Autodesk Fusion 360 part; units mm, degrees
(part 2 of 2)
equation "d66 = ( ( ( layoutGap + keycapSize / 2 + 0 * keyPitch ) - switchOpening / 2 ) + ( switchOpening ) ) - ( ( layoutGap + keycapSize / 2 + 0 * keyPitch ) - switchOpening / 2 )"
equation "d67 = ( ( ( ( keyRowOne ) - switchOpening / 2 ) + faceOriginV ) + ( switchOpening ) ) - ( ( ( keyRowOne ) - switchOpening / 2 ) + faceOriginV )"
equation "d68 = -( carrierThickness + 1 mm )"
equation "d70 = ( layoutGap + keycapSize / 2 + 0 * keyPitch ) - upperSwitchOpening / 2"
equation "d71 = ( ( keyRowOne ) - upperSwitchOpening / 2 ) + faceOriginV"
equation "d72 = ( ( ( layoutGap + keycapSize / 2 + 0 * keyPitch ) - upperSwitchOpening / 2 ) + ( upperSwitchOpening ) ) - ( ( layoutGap + keycapSize / 2 + 0 * keyPitch ) - upperSwitchOpening / 2 )"
equation "d73 = ( ( ( ( keyRowOne ) - upperSwitchOpening / 2 ) + faceOriginV ) + ( upperSwitchOpening ) ) - ( ( ( keyRowOne ) - upperSwitchOpening / 2 ) + faceOriginV )"
equation "d74 = -( shellWall + 1 mm )"
equation "d76 = ( layoutGap + keycapSize / 2 + 1 * keyPitch ) - switchOpening / 2"
equation "d77 = ( ( keyRowOne ) - switchOpening / 2 ) + faceOriginV"
equation "d78 = ( ( ( layoutGap + keycapSize / 2 + 1 * keyPitch ) - switchOpening / 2 ) + ( switchOpening ) ) - ( ( layoutGap + keycapSize / 2 + 1 * keyPitch ) - switchOpening / 2 )"
equation "d79 = ( ( ( ( keyRowOne ) - switchOpening / 2 ) + faceOriginV ) + ( switchOpening ) ) - ( ( ( keyRowOne ) - switchOpening / 2 ) + faceOriginV )"
equation "d80 = -( carrierThickness + 1 mm )"
equation "d82 = ( layoutGap + keycapSize / 2 + 1 * keyPitch ) - upperSwitchOpening / 2"
equation "d83 = ( ( keyRowOne ) - upperSwitchOpening / 2 ) + faceOriginV"
equation "d84 = ( ( ( layoutGap + keycapSize / 2 + 1 * keyPitch ) - upperSwitchOpening / 2 ) + ( upperSwitchOpening ) ) - ( ( layoutGap + keycapSize / 2 + 1 * keyPitch ) - upperSwitchOpening / 2 )"
equation "d85 = ( ( ( ( keyRowOne ) - upperSwitchOpening / 2 ) + faceOriginV ) + ( upperSwitchOpening ) ) - ( ( ( keyRowOne ) - upperSwitchOpening / 2 ) + faceOriginV )"
equation "d86 = -( shellWall + 1 mm )"
equation "d88 = ( layoutGap + keycapSize / 2 + 2 * keyPitch ) - switchOpening / 2"
equation "d89 = ( ( keyRowOne ) - switchOpening / 2 ) + faceOriginV"
equation "d90 = ( ( ( layoutGap + keycapSize / 2 + 2 * keyPitch ) - switchOpening / 2 ) + ( switchOpening ) ) - ( ( layoutGap + keycapSize / 2 + 2 * keyPitch ) - switchOpening / 2 )"
equation "d91 = ( ( ( ( keyRowOne ) - switchOpening / 2 ) + faceOriginV ) + ( switchOpening ) ) - ( ( ( keyRowOne ) - switchOpening / 2 ) + faceOriginV )"
equation "d92 = -( carrierThickness + 1 mm )"
equation "d94 = ( layoutGap + keycapSize / 2 + 2 * keyPitch ) - upperSwitchOpening / 2"
equation "d95 = ( ( keyRowOne ) - upperSwitchOpening / 2 ) + faceOriginV"
equation "d96 = ( ( ( layoutGap + keycapSize / 2 + 2 * keyPitch ) - upperSwitchOpening / 2 ) + ( upperSwitchOpening ) ) - ( ( layoutGap + keycapSize / 2 + 2 * keyPitch ) - upperSwitchOpening / 2 )"
equation "d97 = ( ( ( ( keyRowOne ) - upperSwitchOpening / 2 ) + faceOriginV ) + ( upperSwitchOpening ) ) - ( ( ( keyRowOne ) - upperSwitchOpening / 2 ) + faceOriginV )"
equation "d98 = -( shellWall + 1 mm )"
equation "d100 = ( layoutGap + keycapSize / 2 + 0 * keyPitch ) - switchOpening / 2"
equation "d101 = ( ( keyRowTwo ) - switchOpening / 2 ) + faceOriginV"
equation "d102 = ( ( ( layoutGap + keycapSize / 2 + 0 * keyPitch ) - switchOpening / 2 ) + ( switchOpening ) ) - ( ( layoutGap + keycapSize / 2 + 0 * keyPitch ) - switchOpening / 2 )"
equation "d103 = ( ( ( ( keyRowTwo ) - switchOpening / 2 ) + faceOriginV ) + ( switchOpening ) ) - ( ( ( keyRowTwo ) - switchOpening / 2 ) + faceOriginV )"
equation "d104 = -( carrierThickness + 1 mm )"
equation "d106 = ( layoutGap + keycapSize / 2 + 0 * keyPitch ) - upperSwitchOpening / 2"
equation "d107 = ( ( keyRowTwo ) - upperSwitchOpening / 2 ) + faceOriginV"
equation "d108 = ( ( ( layoutGap + keycapSize / 2 + 0 * keyPitch ) - upperSwitchOpening / 2 ) + ( upperSwitchOpening ) ) - ( ( layoutGap + keycapSize / 2 + 0 * keyPitch ) - upperSwitchOpening / 2 )"
equation "d109 = ( ( ( ( keyRowTwo ) - upperSwitchOpening / 2 ) + faceOriginV ) + ( upperSwitchOpening ) ) - ( ( ( keyRowTwo ) - upperSwitchOpening / 2 ) + faceOriginV )"
equation "d110 = -( shellWall + 1 mm )"
equation "d112 = ( layoutGap + keycapSize / 2 + 1 * keyPitch ) - switchOpening / 2"
equation "d113 = ( ( keyRowTwo ) - switchOpening / 2 ) + faceOriginV"
equation "d114 = ( ( ( layoutGap + keycapSize / 2 + 1 * keyPitch ) - switchOpening / 2 ) + ( switchOpening ) ) - ( ( layoutGap + keycapSize / 2 + 1 * keyPitch ) - switchOpening / 2 )"
equation "d115 = ( ( ( ( keyRowTwo ) - switchOpening / 2 ) + faceOriginV ) + ( switchOpening ) ) - ( ( ( keyRowTwo ) - switchOpening / 2 ) + faceOriginV )"
equation "d116 = -( carrierThickness + 1 mm )"
equation "d118 = ( layoutGap + keycapSize / 2 + 1 * keyPitch ) - upperSwitchOpening / 2"
equation "d119 = ( ( keyRowTwo ) - upperSwitchOpening / 2 ) + faceOriginV"
equation "d120 = ( ( ( layoutGap + keycapSize / 2 + 1 * keyPitch ) - upperSwitchOpening / 2 ) + ( upperSwitchOpening ) ) - ( ( layoutGap + keycapSize / 2 + 1 * keyPitch ) - upperSwitchOpening / 2 )"
equation "d121 = ( ( ( ( keyRowTwo ) - upperSwitchOpening / 2 ) + faceOriginV ) + ( upperSwitchOpening ) ) - ( ( ( keyRowTwo ) - upperSwitchOpening / 2 ) + faceOriginV )"
equation "d122 = -( shellWall + 1 mm )"
equation "d124 = ( layoutGap + keycapSize / 2 + 2 * keyPitch ) - switchOpening / 2"
equation "d125 = ( ( keyRowTwo ) - switchOpening / 2 ) + faceOriginV"
equation "d126 = ( ( ( layoutGap + keycapSize / 2 + 2 * keyPitch ) - switchOpening / 2 ) + ( switchOpening ) ) - ( ( layoutGap + keycapSize / 2 + 2 * keyPitch ) - switchOpening / 2 )"
equation "d127 = ( ( ( ( keyRowTwo ) - switchOpening / 2 ) + faceOriginV ) + ( switchOpening ) ) - ( ( ( keyRowTwo ) - switchOpening / 2 ) + faceOriginV )"
equation "d128 = -( carrierThickness + 1 mm )"
equation "d130 = ( layoutGap + keycapSize / 2 + 2 * keyPitch ) - upperSwitchOpening / 2"
equation "d131 = ( ( keyRowTwo ) - upperSwitchOpening / 2 ) + faceOriginV"
equation "d132 = ( ( ( layoutGap + keycapSize / 2 + 2 * keyPitch ) - upperSwitchOpening / 2 ) + ( upperSwitchOpening ) ) - ( ( layoutGap + keycapSize / 2 + 2 * keyPitch ) - upperSwitchOpening / 2 )"
equation "d133 = ( ( ( ( keyRowTwo ) - upperSwitchOpening / 2 ) + faceOriginV ) + ( upperSwitchOpening ) ) - ( ( ( keyRowTwo ) - upperSwitchOpening / 2 ) + faceOriginV )"
equation "d134 = -( shellWall + 1 mm )"
equation "d136 = ( caseWidth - ledWidth ) / 2"
equation "d137 = ( ledCenter - ledHeight / 2 ) + faceOriginV"
equation "d138 = ( ( ( caseWidth - ledWidth ) / 2 ) + ( ledWidth ) ) - ( ( caseWidth - ledWidth ) / 2 )"
equation "d139 = ( ( ( ledCenter - ledHeight / 2 ) + faceOriginV ) + ( ledHeight ) ) - ( ( ledCenter - ledHeight / 2 ) + faceOriginV )"
equation "d140 = -( shellWall + 1 mm )"
equation "d142 = layoutGap"
equation "d143 = ( controlCenter - displayHeight / 2 ) + faceOriginV"
equation "d144 = ( ( layoutGap ) + ( displayWidth ) ) - ( layoutGap )"
equation "d145 = ( ( ( controlCenter - displayHeight / 2 ) + faceOriginV ) + ( displayHeight ) ) - ( ( controlCenter - displayHeight / 2 ) + faceOriginV )"
equation "d146 = -( shellWall + 1 mm )"
equation "d148 = encoderCenterX"
equation "d149 = controlCenter + faceOriginV"
equation "d150 = encoderHole"
equation "d151 = -( shellWall + 1 mm )"
equation "d153 = ( ( 0 mm ) + ( caseWidth ) ) - ( 0 mm )"
equation "d154 = ( ( 0 mm ) + ( caseLength ) ) - ( 0 mm )"
equation "d155 = bottomThickness"
equation "d157 = ( caseWidth - ledWidth ) / 2 + diffuserClearance"
equation "d158 = ( ledCenter - ledHeight / 2 + diffuserClearance ) + faceOriginV"
equation "d159 = ( ( ( caseWidth - ledWidth ) / 2 + diffuserClearance ) + ( ledWidth - 2 * diffuserClearance ) ) - ( ( caseWidth - ledWidth ) / 2 + diffuserClearance )"
equation "d160 = ( ( ( ledCenter - ledHeight / 2 + diffuserClearance ) + faceOriginV ) + ( ledHeight - 2 * diffuserClearance ) ) - ( ( ledCenter - ledHeight / 2 + diffuserClearance ) + faceOriginV )"
equation "d161 = -( shellWall )"
equation "d163 = -shellWall"
equation "d165 = ( caseWidth - ledWidth ) / 2 + diffuserClearance - diffuserFlange"
equation "d166 = ( ledCenter - ledHeight / 2 + diffuserClearance - diffuserFlange ) + faceOriginV"
equation "d167 = ( ( ( caseWidth - ledWidth ) / 2 + diffuserClearance - diffuserFlange ) + ( ledWidth - 2 * diffuserClearance + 2 * diffuserFlange ) ) - ( ( caseWidth - ledWidth ) / 2 + diffuserClearance - diffuserFlange )"
equation "d168 = ( ( ( ledCenter - ledHeight / 2 + diffuserClearance - diffuserFlange ) + faceOriginV ) + ( ledHeight - 2 * diffuserClearance + 2 * diffuserFlange ) ) - ( ( ledCenter - ledHeight / 2 + diffuserClearance - diffuserFlange ) + faceOriginV )"
equation "d169 = -( diffuserFlangeThickness )"
equation "carrierFaceLength = faceLength - 2 * ( shellWall + carrierClearance ) / cos(caseTilt) - carrierThickness * tan(caseTilt)" comment "Carrier rear clearance"
equation "d172 = layoutGap + 0 * keyPitch"
equation "d173 = ( keyRowOne - keycapSize / 2 ) + faceOriginV"
equation "d174 = ( ( layoutGap + 0 * keyPitch ) + ( keycapSize ) ) - ( layoutGap + 0 * keyPitch )"
equation "d175 = ( ( ( keyRowOne - keycapSize / 2 ) + faceOriginV ) + ( keycapSize ) ) - ( ( keyRowOne - keycapSize / 2 ) + faceOriginV )"
equation "d176 = layoutGap + 1 * keyPitch"
equation "d177 = ( keyRowOne - keycapSize / 2 ) + faceOriginV"
equation "d178 = ( ( layoutGap + 1 * keyPitch ) + ( keycapSize ) ) - ( layoutGap + 1 * keyPitch )"
equation "d179 = ( ( ( keyRowOne - keycapSize / 2 ) + faceOriginV ) + ( keycapSize ) ) - ( ( keyRowOne - keycapSize / 2 ) + faceOriginV )"
equation "d180 = layoutGap + 2 * keyPitch"
equation "d181 = ( keyRowOne - keycapSize / 2 ) + faceOriginV"
equation "d182 = ( ( layoutGap + 2 * keyPitch ) + ( keycapSize ) ) - ( layoutGap + 2 * keyPitch )"
equation "d183 = ( ( ( keyRowOne - keycapSize / 2 ) + faceOriginV ) + ( keycapSize ) ) - ( ( keyRowOne - keycapSize / 2 ) + faceOriginV )"
equation "d184 = layoutGap + 0 * keyPitch"
equation "d185 = ( keyRowTwo - keycapSize / 2 ) + faceOriginV"
equation "d186 = ( ( layoutGap + 0 * keyPitch ) + ( keycapSize ) ) - ( layoutGap + 0 * keyPitch )"
equation "d187 = ( ( ( keyRowTwo - keycapSize / 2 ) + faceOriginV ) + ( keycapSize ) ) - ( ( keyRowTwo - keycapSize / 2 ) + faceOriginV )"
equation "d188 = layoutGap + 1 * keyPitch"
equation "d189 = ( keyRowTwo - keycapSize / 2 ) + faceOriginV"
equation "d190 = ( ( layoutGap + 1 * keyPitch ) + ( keycapSize ) ) - ( layoutGap + 1 * keyPitch )"
equation "d191 = ( ( ( keyRowTwo - keycapSize / 2 ) + faceOriginV ) + ( keycapSize ) ) - ( ( keyRowTwo - keycapSize / 2 ) + faceOriginV )"
equation "d192 = layoutGap + 2 * keyPitch"
equation "d193 = ( keyRowTwo - keycapSize / 2 ) + faceOriginV"
equation "d194 = ( ( layoutGap + 2 * keyPitch ) + ( keycapSize ) ) - ( layoutGap + 2 * keyPitch )"
equation "d195 = ( ( ( keyRowTwo - keycapSize / 2 ) + faceOriginV ) + ( keycapSize ) ) - ( ( keyRowTwo - keycapSize / 2 ) + faceOriginV )"
equation "d196 = encoderCenterX"
equation "d197 = controlCenter + faceOriginV"
equation "d198 = encoderKnobDiameter"
equation "flangePocketClearance = 0.2 mm" comment "Carrier pocket clearance"
equation "d200 = ( caseWidth - ledWidth ) / 2 + diffuserClearance - diffuserFlange - flangePocketClearance"
equation "d201 = ( ledCenter - ledHeight / 2 + diffuserClearance - diffuserFlange - flangePocketClearance ) + faceOriginV"
equation "d202 = ( ( ( caseWidth - ledWidth ) / 2 + diffuserClearance - diffuserFlange - flangePocketClearance ) + ( ledWidth - 2 * diffuserClearance + 2 * diffuserFlange + 2 * flangePocketClearance ) ) - ( ( caseWidth - ledWidth ) / 2 + diffuserClearance - diffuserFlange - flangePocketClearance )"
equation "d203 = ( ( ( ledCenter - ledHeight / 2 + diffuserClearance - diffuserFlange - flangePocketClearance ) + faceOriginV ) + ( ledHeight - 2 * diffuserClearance + 2 * diffuserFlange + 2 * flangePocketClearance ) ) - ( ( ledCenter - ledHeight / 2 + diffuserClearance - diffuserFlange - flangePocketClearance ) + faceOriginV )"
equation "d204 = -( diffuserFlangeThickness - carrierClearance + flangePocketClearance )"
equation "carrierBayWidth = min(caseWidth - 2 * ( shellWall + carrierClearance + carrierRim ); ledWidth - 2 * diffuserClearance + 2 * diffuserFlange - 2 mm)" comment "Electronics opening preserving diffuser support rails"
equation "mountSideX = 4.8 mm" comment "Carrier fastener center from side"
equation "mountFrontV = 8 mm" comment "Front fastener center in face coordinates"
equation "mountRearV = faceLength - 8.4 mm" comment "Rear fastener center in face coordinates"
equation "mountBossDiameter = 7 mm" comment "Wall-connected M2 boss diameter"
equation "insertLength = 4 mm" comment "Confirmed M2 insert length"
equation "insertOuterDiameter = 3.5 mm" comment "Confirmed M2 insert outer diameter"
equation "insertPilotDiameter = 3.2 mm" comment "Provisional PLA pilot; test coupon required"
equation "insertPilotDepth = insertLength + 0.5 mm" comment "Blind insert pocket depth"
equation "carrierBossDepth = 7.4 mm" comment "Shell boss bottom below exterior face"
equation "carrierPadDepth = 10 mm" comment "Carrier pad bottom below exterior face"
equation "mountPocketClearance = 0.3 mm + ( carrierBossDepth - shellWall - carrierClearance ) * tan(caseTilt)" comment "Per-side carrier boss clearance"
equation "mountPadWidth = 7.8 mm" comment "Carrier mounting pad width"
equation "mountPadLength = 9.4 mm" comment "Carrier mounting pad length"
equation "m2Clearance = 2.3 mm" comment "Draft M2 screw clearance"
equation "bottomBossHeight = 6 mm" comment "Independent cover boss height above lid"
equation "carrierRibWidth = 2 mm" comment "Switch-field reinforcing rib width"
equation "carrierRibDepth = 3 mm" comment "Reinforcement below switch plate"
equation "d224 = -carrierBossDepth"
equation "d226 = -( carrierBossDepth + carrierClearance )"
equation "d228 = bottomThickness"
equation "d230 = mountSideX"
equation "d231 = ( mountFrontV ) + faceOriginV"
equation "d232 = mountBossDiameter"
equation "d233 = -( carrierBossDepth )"
equation "d235 = mountSideX"
equation "d236 = ( mountFrontV ) + faceOriginV"
equation "d237 = insertPilotDiameter"
equation "d238 = insertPilotDepth"
equation "d240 = shellWall + carrierClearance"
equation "d241 = ( ( mountFrontV ) - mountPadLength / 2 ) + faceOriginV"
equation "d242 = ( ( shellWall + carrierClearance ) + ( mountPadWidth ) ) - ( shellWall + carrierClearance )"
equation "d243 = ( ( ( ( mountFrontV ) - mountPadLength / 2 ) + faceOriginV ) + ( mountPadLength ) ) - ( ( ( mountFrontV ) - mountPadLength / 2 ) + faceOriginV )"
equation "d244 = -( carrierPadDepth - shellWall - carrierClearance )"
equation "d246 = mountSideX"
equation "d247 = ( mountFrontV ) + faceOriginV"
equation "d248 = mountBossDiameter + 2 * mountPocketClearance"
equation "d249 = carrierBossDepth + carrierClearance"
equation "d251 = mountSideX"
equation "d252 = ( mountFrontV ) + faceOriginV"
equation "d253 = m2Clearance"
equation "d254 = -( carrierPadDepth )"
equation "d258 = bottomBossDiameter"
equation "d259 = bottomBossHeight"
equation "d263 = insertPilotDiameter"
equation "d264 = insertPilotDepth"
equation "d268 = m2Clearance"
equation "d269 = -( bottomThickness + 0.5 mm )"
equation "d271 = caseWidth - mountSideX"
equation "d272 = ( mountFrontV ) + faceOriginV"
equation "d273 = mountBossDiameter"
equation "d274 = -( carrierBossDepth )"
equation "d276 = caseWidth - mountSideX"
equation "d277 = ( mountFrontV ) + faceOriginV"
equation "d278 = insertPilotDiameter"
equation "d279 = insertPilotDepth"
equation "d281 = caseWidth - shellWall - carrierClearance - mountPadWidth"
equation "d282 = ( ( mountFrontV ) - mountPadLength / 2 ) + faceOriginV"
equation "d283 = ( ( caseWidth - shellWall - carrierClearance - mountPadWidth ) + ( mountPadWidth ) ) - ( caseWidth - shellWall - carrierClearance - mountPadWidth )"
equation "d284 = ( ( ( ( mountFrontV ) - mountPadLength / 2 ) + faceOriginV ) + ( mountPadLength ) ) - ( ( ( mountFrontV ) - mountPadLength / 2 ) + faceOriginV )"
equation "d285 = -( carrierPadDepth - shellWall - carrierClearance )"
equation "d287 = caseWidth - mountSideX"
equation "d288 = ( mountFrontV ) + faceOriginV"
equation "d289 = mountBossDiameter + 2 * mountPocketClearance"
equation "d290 = carrierBossDepth + carrierClearance"
equation "d292 = caseWidth - mountSideX"
equation "d293 = ( mountFrontV ) + faceOriginV"
equation "d294 = m2Clearance"
equation "d295 = -( carrierPadDepth )"
equation "d297 = caseWidth - 20 mm"
equation "d299 = bottomBossDiameter"
equation "d300 = bottomBossHeight"
equation "d302 = caseWidth - 20 mm"
equation "d304 = insertPilotDiameter"
equation "d305 = insertPilotDepth"
equation "d307 = caseWidth - 20 mm"
equation "d309 = m2Clearance"
equation "d310 = -( bottomThickness + 0.5 mm )"
equation "d312 = mountSideX"
equation "d313 = ( mountRearV ) + faceOriginV"
equation "d314 = mountBossDiameter"
equation "d315 = -( carrierBossDepth )"
equation "d317 = mountSideX"
equation "d318 = ( mountRearV ) + faceOriginV"
equation "d319 = insertPilotDiameter"
equation "d320 = insertPilotDepth"
equation "d322 = shellWall + carrierClearance"
equation "d323 = ( ( mountRearV ) - mountPadLength / 2 ) + faceOriginV"
equation "d324 = ( ( shellWall + carrierClearance ) + ( mountPadWidth ) ) - ( shellWall + carrierClearance )"
equation "d325 = ( ( ( ( mountRearV ) - mountPadLength / 2 ) + faceOriginV ) + ( mountPadLength ) ) - ( ( ( mountRearV ) - mountPadLength / 2 ) + faceOriginV )"
equation "d326 = -( carrierPadDepth - shellWall - carrierClearance )"
equation "d328 = mountSideX"
equation "d329 = ( mountRearV ) + faceOriginV"
equation "d330 = mountBossDiameter + 2 * mountPocketClearance"
equation "d331 = carrierBossDepth + carrierClearance"
equation "d333 = mountSideX"
equation "d334 = ( mountRearV ) + faceOriginV"
equation "d335 = m2Clearance"
equation "d336 = -( carrierPadDepth )"
equation "d338 = mountSideX"
equation "d339 = caseLength - 3 mm"
equation "d340 = bottomBossDiameter"
equation "d341 = bottomBossHeight"
equation "d343 = mountSideX"
equation "d344 = caseLength - 3 mm"
equation "d345 = insertPilotDiameter"
equation "d346 = insertPilotDepth"
equation "d348 = mountSideX"
equation "d349 = caseLength - 3 mm"
equation "d350 = m2Clearance"
equation "d351 = -( bottomThickness + 0.5 mm )"
equation "d353 = caseWidth - mountSideX"
equation "d354 = ( mountRearV ) + faceOriginV"
equation "d355 = mountBossDiameter"
equation "d356 = -( carrierBossDepth )"
equation "d358 = caseWidth - mountSideX"
equation "d359 = ( mountRearV ) + faceOriginV"
equation "d360 = insertPilotDiameter"
equation "d361 = insertPilotDepth"
equation "d363 = caseWidth - shellWall - carrierClearance - mountPadWidth"
equation "d364 = ( ( mountRearV ) - mountPadLength / 2 ) + faceOriginV"
equation "d365 = ( ( caseWidth - shellWall - carrierClearance - mountPadWidth ) + ( mountPadWidth ) ) - ( caseWidth - shellWall - carrierClearance - mountPadWidth )"
equation "d366 = ( ( ( ( mountRearV ) - mountPadLength / 2 ) + faceOriginV ) + ( mountPadLength ) ) - ( ( ( mountRearV ) - mountPadLength / 2 ) + faceOriginV )"
equation "d367 = -( carrierPadDepth - shellWall - carrierClearance )"
equation "d369 = caseWidth - mountSideX"
equation "d370 = ( mountRearV ) + faceOriginV"
equation "d371 = mountBossDiameter + 2 * mountPocketClearance"
equation "d372 = carrierBossDepth + carrierClearance"
equation "d374 = caseWidth - mountSideX"
equation "d375 = ( mountRearV ) + faceOriginV"
equation "d376 = m2Clearance"
equation "d377 = -( carrierPadDepth )"
equation "d379 = caseWidth - mountSideX"
equation "d380 = caseLength - 3 mm"
equation "d381 = bottomBossDiameter"
equation "d382 = bottomBossHeight"
equation "d384 = caseWidth - mountSideX"
equation "d385 = caseLength - 3 mm"
equation "d386 = insertPilotDiameter"
equation "d387 = insertPilotDepth"
equation "d389 = caseWidth - mountSideX"
equation "d390 = caseLength - 3 mm"
equation "d391 = m2Clearance"
equation "d392 = -( bottomThickness + 0.5 mm )"
equation "d394 = ( layoutGap + keycapSize / 2 + ( 0 + 0.5 ) * keyPitch ) - carrierRibWidth / 2"
equation "d395 = ( mountFrontV + mountPadLength / 2 ) + faceOriginV"
equation "d396 = ( ( ( layoutGap + keycapSize / 2 + ( 0 + 0.5 ) * keyPitch ) - carrierRibWidth / 2 ) + ( carrierRibWidth ) ) - ( ( layoutGap + keycapSize / 2 + ( 0 + 0.5 ) * keyPitch ) - carrierRibWidth / 2 )"
equation "d397 = ( ( ( mountFrontV + mountPadLength / 2 ) + faceOriginV ) + ( keyRowTwo + keycapSize / 2 + 1 mm - mountFrontV - mountPadLength / 2 ) ) - ( ( mountFrontV + mountPadLength / 2 ) + faceOriginV )"
equation "d398 = -( carrierThickness + carrierRibDepth )"
equation "d400 = ( layoutGap + keycapSize / 2 + ( 1 + 0.5 ) * keyPitch ) - carrierRibWidth / 2"
equation "d401 = ( mountFrontV + mountPadLength / 2 ) + faceOriginV"
equation "d402 = ( ( ( layoutGap + keycapSize / 2 + ( 1 + 0.5 ) * keyPitch ) - carrierRibWidth / 2 ) + ( carrierRibWidth ) ) - ( ( layoutGap + keycapSize / 2 + ( 1 + 0.5 ) * keyPitch ) - carrierRibWidth / 2 )"
equation "d403 = ( ( ( mountFrontV + mountPadLength / 2 ) + faceOriginV ) + ( keyRowTwo + keycapSize / 2 + 1 mm - mountFrontV - mountPadLength / 2 ) ) - ( ( mountFrontV + mountPadLength / 2 ) + faceOriginV )"
equation "d404 = -( carrierThickness + carrierRibDepth )"
equation "d407 = ( ( keyRowOne + keyRowTwo ) / 2 - carrierRibWidth / 2 ) + faceOriginV"
equation "d408 = ( ( 10 mm ) + ( caseWidth - 20 mm ) ) - ( 10 mm )"
equation "d409 = ( ( ( ( keyRowOne + keyRowTwo ) / 2 - carrierRibWidth / 2 ) + faceOriginV ) + ( carrierRibWidth ) ) - ( ( ( keyRowOne + keyRowTwo ) / 2 - carrierRibWidth / 2 ) + faceOriginV )"
equation "d410 = -( carrierThickness + carrierRibDepth )"
equation "bottomBossDiameter = 6 mm" comment "Cover boss diameter; corner insertion relief"
equation "bottomReliefClearance = 0.2 mm" comment "Radial clearance for carrier removal past cover bosses"
equation "d416 = bottomBossDiameter + 2 * bottomReliefClearance"
equation "d417 = rearHeight + 1 mm"
equation "d419 = caseWidth - 20 mm"
equation "d421 = bottomBossDiameter + 2 * bottomReliefClearance"
equation "d422 = rearHeight + 1 mm"
equation "d424 = mountSideX"
equation "d425 = caseLength - 3 mm"
equation "d426 = bottomBossDiameter + 2 * bottomReliefClearance"
equation "d427 = rearHeight + 1 mm"
equation "d429 = caseWidth - mountSideX"
equation "d430 = caseLength - 3 mm"
equation "d431 = bottomBossDiameter + 2 * bottomReliefClearance"
equation "d432 = rearHeight + 1 mm"
equation "pcbWidth = 70 mm" comment "Confirmed board width"
equation "pcbLength = 50 mm" comment "Confirmed board length"
equation "pcbThickness = 1.6 mm" comment "Confirmed board thickness"
equation "pcbHolePitchX = 66 mm" comment "Confirmed hole center spacing across board"
equation "pcbHolePitchY = 46 mm" comment "Confirmed hole center spacing along board"
equation "pcbRearGap = 0.4 mm" comment "Provisional board-to-rear-wall clearance"
equation "pcbUndersideHeight = bottomThickness + bottomBossHeight + 0.8 mm" comment "Provisional PCB underside, clearing lower bosses"
equation "pcbTopHeight = pcbUndersideHeight + pcbThickness" comment "PCB top reference"
equation "pcbLeft = ( caseWidth - pcbWidth ) / 2" comment "Centered board left edge"
equation "pcbRear = caseLength - shellWall - pcbRearGap" comment "Board rear edge"
equation "pcbFront = pcbRear - pcbLength" comment "Board front edge"
equation "usbCenterX = pcbLeft + 36 mm" comment "Confirmed USB center from board left edge"
equation "usbCenterZ = pcbTopHeight + 5.5 mm" comment "USB center above PCB top"
equation "headerMaxHeight = 17 mm" comment "Local header envelope; footprints pending"
equation "d448 = pcbUndersideHeight"
equation "d450 = pcbTopHeight"
equation "d452 = pcbLeft"
equation "d453 = pcbFront"
equation "d454 = ( ( pcbLeft ) + ( pcbWidth ) ) - ( pcbLeft )"
equation "d455 = ( ( pcbFront ) + ( pcbLength ) ) - ( pcbFront )"
equation "d456 = pcbLeft"
equation "d457 = pcbFront"
equation "d458 = ( ( pcbLeft ) + ( pcbWidth ) ) - ( pcbLeft )"
equation "d459 = ( ( pcbFront ) + ( pcbLength ) ) - ( pcbFront )"
equation "d460 = pcbLeft + ( pcbWidth - pcbHolePitchX ) / 2 + 0 * pcbHolePitchX"
equation "d461 = pcbFront + ( pcbLength - pcbHolePitchY ) / 2 + 0 * pcbHolePitchY"
equation "d462 = pcbLeft + ( pcbWidth - pcbHolePitchX ) / 2 + 1 * pcbHolePitchX"
equation "d463 = pcbFront + ( pcbLength - pcbHolePitchY ) / 2 + 0 * pcbHolePitchY"
equation "d464 = pcbLeft + ( pcbWidth - pcbHolePitchX ) / 2 + 0 * pcbHolePitchX"
equation "d465 = pcbFront + ( pcbLength - pcbHolePitchY ) / 2 + 1 * pcbHolePitchY"
equation "d466 = pcbLeft + ( pcbWidth - pcbHolePitchX ) / 2 + 1 * pcbHolePitchX"
equation "d467 = pcbFront + ( pcbLength - pcbHolePitchY ) / 2 + 1 * pcbHolePitchY"
equation "headerRoutingTarget = 14 mm" comment "Conditional mated header and wire envelope; physical verification required"
equation "xh3Length = 10 mm" comment "Measured 3-pin connector length"
equation "xh4Length = 13 mm" comment "Measured 4-pin connector length"
equation "xh5Length = 15 mm" comment "Measured 5-pin connector length"
equation "sideHeaderInset = 3 mm" comment "User-supplied side header inset; reference edge to verify"
named bodies: "UpperShell_Draft", "MiddleCarrier_Draft", "BottomCover_Draft", "Diffuser_Draft"
